Autodesk Fusion 360 part; units mm, degrees
(part 9 of 18)
  line L6313 (33.9045, -153.151) -> (33.4411, -152.779)
  line L6314 (19.1589, -158.41) -> (19.2769, -157.837)
  line L6315 (140.963, -49.9272) -> (141.518, -49.7173)
  line L6316 (23.0175, -167.339) -> (23.5183, -167.658)
  line L6317 (141.518, -49.7173) -> (142.059, -49.4711)
  line L6318 (42.7274, -154.669) -> (43.0836, -154.206)
  line L6319 (140.395, -50.0999) -> (140.963, -49.9272)
  line L6320 (23.3845, -152.323) -> (22.8893, -152.651)
  line L6321 (129.344, -157.966) -> (129.232, -158.549)
  line L6322 (146.218, -37.4969) -> (146.456, -38.0305)
  line L6323 (19.2578, -161.505) -> (19.3803, -162.086)
  line L6324 (129.38, -43.5861) -> (129.541, -44.1577)
  line L6325 (30.9627, -168.427) -> (31.5182, -168.217)
  line L6326 (41.2321, -63.7491) -> (41.1587, -64.3384)
  line L6327 (35.1334, -154.437) -> (34.7525, -153.981)
  line L6328 (146.855, -39.68) -> (146.719, -39.1021)
  line L6329 (24.2951, -151.728) -> (24.8336, -151.501)
  line L6330 (146.719, -39.1021) -> (146.544, -38.5345)
  line L6331 (130.727, -36.169) -> (131.084, -35.7057)
  line L6332 (145.483, -154.917) -> (145.133, -154.437)
  line L6333 (141.373, -151.624) -> (140.814, -151.424)
  line L6334 (41.4315, -157.274) -> (41.6223, -156.722)
  line L6335 (136.927, -50.4266) -> (136.35, -50.3337)
  line L6336 (145.801, -155.418) -> (145.483, -154.917)
  line L6337 (134.834, -33.0011) -> (135.386, -32.8094)
  line L6338 (144.453, -166.238) -> (144.856, -165.801)
  line L6339 (142.711, -33.6764) -> (143.203, -33.9917)
  line L6340 (33.0587, -167.505) -> (32.5607, -167.811)
  line L6341 (146.456, -38.0305) -> (146.659, -38.5784)
  line L6342 (133.62, -49.3267) -> (133.121, -49.0227)
  line L6343 (41.1297, -65.525) -> (41.1742, -66.1171)
  line L6344 (35.8585, -164.57) -> (35.5441, -165.063)
  line L6345 (129.974, -45.2629) -> (130.245, -45.7915)
  line L6346 (147.012, -159.357) -> (146.953, -158.766)
  line L6347 (129.777, -45.0587) -> (129.562, -44.5156)
  line L6348 (138.639, -168.887) -> (139.23, -168.83)
  line L6349 (32.4456, -152.133) -> (31.9179, -151.861)
  line L6350 (135.386, -32.8094) -> (135.949, -32.6538)
  line L6351 (146.758, -43.6467) -> (146.885, -43.0665)
  line L6352 (129.238, -43.3934) -> (129.131, -42.8189)
  line L6353 (141.518, -168.217) -> (142.059, -167.971)
  line L6354 (129.159, -39.9096) -> (129.277, -39.3373)
  line L6355 (146.885, -43.0665) -> (146.972, -42.4793)
  line L6356 (147.027, -42.7877) -> (146.922, -43.3625)
  line L6357 (45.9003, -57.2286) -> (45.3845, -57.5228)
  line L6358 (29.4301, -151.002) -> (30.0047, -151.108)
  line L6359 (146.594, -44.2172) -> (146.758, -43.6467)
  line L6360 (26.35, -168.834) -> (25.7803, -168.704)
  line L6361 (137.296, -151.029) -> (136.707, -151.1)
  line L6362 (134.039, -49.4431) -> (134.578, -49.6931)
  line L6363 (144.856, -165.801) -> (145.229, -165.339)
  line L6364 (26.7068, -151.1) -> (26.1233, -151.211)
  line L6365 (129.078, -40.4883) -> (129.159, -39.9096)
  line L6366 (28.483, -151.004) -> (27.8893, -150.997)
  line L6367 (135.132, -168.407) -> (135.699, -168.583)
  line L6368 (142.059, -167.971) -> (142.581, -167.69)
  line L6369 (132.539, -166.987) -> (133.018, -167.339)
  line L6370 (132.417, -153.01) -> (131.97, -153.401)
  line L6371 (20.466, -155.231) -> (20.17, -155.746)
  line L6372 (137.682, -32.4086) -> (138.266, -32.402)
  line L6373 (145.858, -46.0704) -> (145.544, -46.563)
  line L6374 (136.707, -151.1) -> (136.123, -151.211)
  line L6375 (142.954, -152.44) -> (142.446, -152.133)
  line L6376 (27.0994, -150.953) -> (27.682, -150.909)
  line L6377 (136.276, -50.2221) -> (136.861, -50.3221)
  line L6378 (35.6409, -154.981) -> (35.9457, -155.48)
  line L6379 (32.1995, -151.894) -> (32.7108, -152.176)
  line L6380 (135.699, -50.0835) -> (136.276, -50.2221)
  line L6381 (36.084, -155.94) -> (35.8006, -155.418)
  line L6382 (34.9379, -154.049) -> (35.3045, -154.504)
  line L6383 (142.199, -33.3936) -> (142.711, -33.6764)
  line L6384 (145.229, -46.8393) -> (145.57, -46.3534)
  line L6385 (36.6024, -162.986) -> (36.3887, -163.53)
  line L6386 (36.8847, -161.567) -> (36.9725, -160.979)
  line L6387 (147.021, -160.387) -> (147.032, -159.95)
  line L6388 (41.078, -158.988) -> (41.1589, -158.41)
  line L6389 (136.861, -168.822) -> (137.452, -168.883)
  line L6390 (131.756, -47.927) -> (131.351, -47.5056)
  line L6391 (140.243, -151.261) -> (139.663, -151.137)
  line L6392 (23.6204, -167.827) -> (23.1214, -167.523)
  line L6393 (19.1309, -161.319) -> (19.0612, -160.739)
  line L6394 (143.904, -153.151) -> (143.441, -152.779)
  line L6395 (41.1587, -64.3384) -> (41.1245, -64.9312)
  line L6396 (33.5358, -167.168) -> (33.0587, -167.505)
  line L6397 (129.035, -41.071) -> (129.078, -40.4883)
  line L6398 (21.0836, -154.206) -> (21.4688, -153.766)
  line L6399 (137.452, -50.3832) -> (138.046, -50.4049)
  line L6400 (31.671, -151.644) -> (32.1995, -151.894)
  line L6401 (41.1589, -158.41) -> (41.2769, -157.837)
  line L6402 (144.823, -47.4821) -> (144.42, -47.9049)
  line L6403 (129.029, -41.6553) -> (129.033, -41.2312)
  line L6404 (146.544, -157.035) -> (146.332, -156.48)
  line L6405 (30.2432, -151.261) -> (29.6626, -151.137)
  line L6406 (144.022, -166.647) -> (144.453, -166.238)
  line L6407 (32.0585, -167.971) -> (32.5813, -167.69)
  line L6408 (19.0347, -159.571) -> (19.078, -158.988)
  line L6409 (144.42, -47.9049) -> (143.99, -48.3008)
  line L6410 (19.3443, -157.966) -> (19.232, -158.549)
  line L6411 (43.0836, -154.206) -> (43.4688, -153.766)
  line L6412 (130.55, -46.301) -> (130.888, -46.7892)
  line L6413 (27.2963, -151.029) -> (26.7068, -151.1)
  line L6414 (28.6391, -168.887) -> (29.2302, -168.83)
  line L6415 (147.021, -41.8875) -> (147.032, -41.45)
  line L6416 (129.174, -42.4171) -> (129.258, -43.005)
  line L6417 (19.1297, -160.325) -> (19.1742, -160.917)
  line L6418 (143.203, -33.9917) -> (143.673, -34.338)
  line L6419 (34.0223, -166.647) -> (34.453, -166.238)
  line L6420 (130.466, -155.231) -> (130.17, -155.746)
  line L6421 (32.5607, -167.811) -> (32.0441, -168.084)
  line L6422 (144.453, -47.7378) -> (144.856, -47.3014)
  line L6423 (35.8006, -155.418) -> (35.4833, -154.917)
  line L6424 (37.0274, -161.288) -> (36.9224, -161.862)
  line L6425 (29.075, -151.051) -> (28.483, -151.004)
  line L6426 (26.5208, -151.035) -> (27.0994, -150.953)
  line L6427 (19.541, -162.658) -> (19.7392, -163.217)
  line L6428 (36.7806, -162.429) -> (36.6024, -162.986)
  line L6429 (30.0047, -151.108) -> (30.5713, -151.251)
  line L6430 (131.882, -34.8528) -> (132.32, -34.4668)
  line L6431 (145.57, -46.3534) -> (145.879, -45.846)
  line L6432 (146.332, -156.48) -> (146.084, -155.94)
  line L6433 (131.469, -35.2664) -> (131.882, -34.8528)
  line L6434 (146.659, -38.5784) -> (146.827, -39.1382)
  line L6435 (25.9488, -151.154) -> (26.5208, -151.035)
  line L6436 (23.1214, -167.523) -> (22.643, -167.187)
  line L6437 (129.258, -43.005) -> (129.38, -43.5861)
  line L6438 (19.1742, -160.917) -> (19.2578, -161.505)
  line L6439 (147.012, -40.8565) -> (146.953, -40.2656)
  line L6440 (34.7525, -153.981) -> (34.3423, -153.552)
  line L6441 (132.643, -48.6871) -> (132.187, -48.3214)
  line L6442 (20.402, -155.154) -> (20.7274, -154.669)
  line L6443 (21.2572, -165.754) -> (21.6569, -166.193)
  line L6444 (147.108, -40.866) -> (147.127, -41.45)
  line L6445 (131.657, -166.193) -> (132.085, -166.605)
  line L6446 (143.565, -48.5258) -> (144.022, -48.1465)
  line L6447 (21.4688, -153.766) -> (21.8816, -153.353)
  line L6448 (129.033, -41.2312) -> (129.035, -41.071)
  line L6449 (140.814, -151.424) -> (140.243, -151.261)
  line L6450 (30.8143, -151.424) -> (30.2432, -151.261)
  line L6451 (132.187, -48.3214) -> (131.756, -47.927)
  line L6452 (145.641, -36.4813) -> (145.946, -36.9798)
  line L6453 (31.3734, -151.624) -> (30.8143, -151.424)
  line L6454 (129.277, -39.3373) -> (129.432, -38.7738)
  line L6455 (143.059, -49.0054) -> (142.561, -49.3111)
  line L6456 (133.121, -49.0227) -> (132.643, -48.6871)
  line L6457 (133.772, -33.4892) -> (134.295, -33.228)
  line L6458 (20.2446, -164.291) -> (20.5495, -164.801)
  line L6459 (136.35, -50.3337) -> (135.78, -50.2038)
  line L6460 (143.536, -48.6681) -> (143.059, -49.0054)
  line L6461 (135.699, -168.583) -> (136.276, -168.722)
  line L6462 (19.4315, -157.274) -> (19.6222, -156.722)
  line L6463 (22.0847, -166.605) -> (22.539, -166.987)
  line L6464 (20.1085, -155.66) -> (20.402, -155.154)
  line L6465 (20.9746, -165.559) -> (20.6274, -165.089)
  line L6466 (129.683, -156.829) -> (129.495, -157.392)
  line L6467 (133.518, -167.658) -> (134.039, -167.943)
  line L6468 (142.561, -49.3111) -> (142.044, -49.5841)
  line L6469 (43.157, -59.466) -> (42.7955, -59.9371)
  line L6470 (147.051, -40.2844) -> (147.108, -40.866)
  line L6471 (132.539, -48.4873) -> (133.018, -48.8389)
  line L6472 (141.128, -32.9297) -> (141.671, -33.1443)
  line L6473 (146.544, -38.5345) -> (146.332, -37.9798)
  line L6474 (132.32, -34.4668) -> (132.783, -34.1099)
  line L6475 (133.385, -152.323) -> (132.889, -152.651)
  line L6476 (35.1986, -165.534) -> (34.8234, -165.982)
  line L6477 (41.1245, -64.9312) -> (41.1297, -65.525)
  line L6478 (35.57, -164.853) -> (35.8785, -164.346)
  line L6479 (25.6987, -168.583) -> (26.2761, -168.722)
  line L6480 (42.17, -60.9459) -> (41.9088, -61.4791)
  line L6481 (19.9741, -163.763) -> (20.2446, -164.291)
  line L6482 (131.351, -47.5056) -> (130.975, -47.059)
  line L6483 (20.7955, -154.737) -> (20.466, -155.231)
  line L6484 (163.518, -168.217) -> (164.059, -167.971)
  line L6485 (164.446, -152.133) -> (163.918, -151.861)
  line L6486 (45.9003, -152.029) -> (45.3845, -152.323)
  line L6487 (81.0274, -161.288) -> (80.9224, -161.862)
  line L6488 (163.671, -151.644) -> (164.199, -151.894)
  line L6489 (66.539, -166.987) -> (67.0175, -167.339)
  line L6490 (152.245, -164.291) -> (152.55, -164.801)
  line L6491 (112.672, -168.335) -> (112.138, -168.098)
  line L6492 (46.4345, -151.769) -> (45.9003, -152.029)
  line L6493 (151.035, -159.571) -> (151.078, -158.988)
  line L6494 (58.1527, -163.819) -> (58.3914, -163.276)
  line L6495 (151.495, -157.392) -> (151.344, -157.966)
  line L6496 (151.124, -159.731) -> (151.13, -160.325)
  line L6497 (63.2379, -161.893) -> (63.1309, -161.319)
  line L6498 (78.453, -166.238) -> (78.8557, -165.801)
  line L6499 (80.3321, -156.48) -> (80.084, -155.94)
  line L6500 (58.9725, -160.979) -> (59.0211, -160.387)
  line L6501 (166.342, -153.552) -> (165.904, -153.151)
  line L6502 (125.127, -159.95) -> (125.125, -160.124)
  line L6503 (58.3914, -163.276) -> (58.5935, -162.717)
  line L6504 (159.296, -151.029) -> (158.707, -151.1)
  line L6505 (73.8346, -168.828) -> (73.2581, -168.923)
  line L6506 (168.602, -162.986) -> (168.389, -163.53)
  line L6507 (49.2963, -151.029) -> (48.7068, -151.1)
  line L6508 (71.4521, -168.883) -> (72.0455, -168.905)
  line L6509 (124.781, -162.429) -> (124.602, -162.986)
  line L6510 (117.835, -168.828) -> (117.258, -168.923)
  line L6511 (46.9847, -151.546) -> (46.4345, -151.769)
  line L6512 (160.677, -168.98) -> (160.093, -169)
  line L6513 (47.5484, -151.359) -> (46.9847, -151.546)
  line L6514 (63.9741, -163.763) -> (64.2446, -164.291)
  line L6515 (48.1233, -151.211) -> (47.5484, -151.359)
  line L6516 (72.6391, -168.887) -> (73.2302, -168.83)
  line L6517 (48.7068, -151.1) -> (48.1233, -151.211)
  line L6518 (168.719, -157.602) -> (168.544, -157.035)
  line L6519 (115.509, -168.982) -> (114.927, -168.927)
  line L6520 (156.672, -168.335) -> (156.138, -168.098)
  line L6521 (65.8816, -153.353) -> (66.3203, -152.967)
  line L6522 (81.0514, -158.784) -> (81.1079, -159.366)
  line L6523 (53.3734, -151.624) -> (52.8143, -151.424)
  line L6524 (151.174, -160.917) -> (151.258, -161.505)
  line L6525 (156.039, -167.943) -> (156.578, -168.193)
  line L6526 (161.258, -168.923) -> (160.677, -168.98)
  line L6527 (123.544, -165.063) -> (123.199, -165.534)
  line L6528 (169.125, -160.124) -> (169.095, -160.707)
  line L6529 (151.277, -157.837) -> (151.432, -157.274)
  line L6530 (151.078, -158.988) -> (151.159, -158.41)
  line L6531 (69.3856, -151.309) -> (69.9488, -151.154)
  line L6532 (151.159, -159.138) -> (151.124, -159.731)
  line L6533 (166.856, -165.801) -> (167.229, -165.339)
  line L6534 (151.159, -158.41) -> (151.277, -157.837)
  line L6535 (80.5935, -162.717) -> (80.7582, -162.147)
  line L6536 (120.044, -168.084) -> (119.511, -168.323)
  line L6537 (153.257, -165.754) -> (153.657, -166.193)
  line L6538 (151.432, -157.274) -> (151.622, -156.722)
  line L6539 (158.861, -168.822) -> (159.452, -168.883)
  line L6540 (65.2572, -165.754) -> (65.6569, -166.193)
  line L6541 (151.033, -159.731) -> (151.035, -159.571)
  line L6542 (79.6409, -154.981) -> (79.9457, -155.48)
  line L6543 (124.922, -161.862) -> (124.781, -162.429)
  line L6544 (66.7829, -152.61) -> (67.2676, -152.284)
  line L6545 (51.6626, -151.137) -> (51.075, -151.051)
  line L6546 (168.781, -162.429) -> (168.602, -162.986)
  line L6547 (55.9045, -153.151) -> (55.4411, -152.779)
  line L6548 (168.544, -157.035) -> (168.332, -156.48)
  line L6549 (80.3887, -163.53) -> (80.1404, -164.059)
  line L6550 (41.1297, -160.325) -> (41.1742, -160.917)
  line L6551 (168.456, -156.531) -> (168.659, -157.078)
  line L6552 (77.9903, -166.801) -> (77.5358, -167.168)
  line L6553 (155.121, -167.523) -> (154.643, -167.187)
  line L6554 (80.7582, -162.147) -> (80.8847, -161.567)
  line L6555 (41.1245, -159.731) -> (41.1297, -160.325)
  line L6556 (154.085, -166.605) -> (154.539, -166.987)
  line L6557 (125.051, -158.784) -> (125.108, -159.366)
  line L6558 (68.672, -168.335) -> (68.138, -168.098)
  line L6559 (67.7724, -151.989) -> (68.2951, -151.728)
  line L6560 (151.232, -158.549) -> (151.159, -159.138)
  line L6561 (157.22, -168.537) -> (156.672, -168.335)
  line L6562 (154.417, -153.01) -> (153.97, -153.401)
  line L6563 (166.823, -165.982) -> (166.42, -166.405)
  line L6564 (69.9488, -151.154) -> (70.5208, -151.035)
  line L6565 (63.078, -158.988) -> (63.1589, -158.41)
  line L6566 (73.8162, -168.734) -> (74.3945, -168.6)
  line L6567 (80.4559, -156.531) -> (80.6591, -157.078)
  line L6568 (41.1587, -159.138) -> (41.1245, -159.731)
  line L6569 (162.963, -168.527) -> (162.404, -168.696)
  line L6570 (168.957, -158.208) -> (169.051, -158.784)
  line L6571 (81.0121, -159.357) -> (80.9531, -158.766)
  line L6572 (155.518, -167.658) -> (156.039, -167.943)
  line L6573 (80.7806, -162.429) -> (80.6024, -162.986)
  line L6574 (63.4315, -157.274) -> (63.6222, -156.722)
  line L6575 (80.2178, -155.997) -> (80.4559, -156.531)
  line L6576 (53.9179, -151.861) -> (53.3734, -151.624)
  line L6577 (113.22, -168.537) -> (112.672, -168.335)
  line L6578 (79.1986, -165.534) -> (78.8234, -165.982)
  line L6579 (79.8585, -164.57) -> (79.5441, -165.063)
  line L6580 (159.889, -150.997) -> (159.296, -151.029)
  line L6581 (168.885, -161.567) -> (168.972, -160.979)
  line L6582 (81.0318, -159.95) -> (81.0121, -159.357)
  line L6583 (54.4456, -152.133) -> (53.9179, -151.861)
  line L6584 (80.9531, -158.766) -> (80.8551, -158.18)
  line L6585 (168.389, -163.53) -> (168.14, -164.059)
  line L6586 (80.6024, -162.986) -> (80.3887, -163.53)
  line L6587 (54.954, -152.44) -> (54.4456, -152.133)
  line L6588 (164.199, -151.894) -> (164.711, -152.176)
  line L6589 (41.2321, -158.549) -> (41.1587, -159.138)
  line L6590 (153.756, -166.427) -> (153.351, -166.006)
  line L6591 (73.4301, -151.002) -> (74.0047, -151.108)
  line L6592 (159.452, -168.883) -> (160.046, -168.905)
  line L6593 (68.8336, -151.501) -> (69.3856, -151.309)
  line L6594 (52.2432, -151.261) -> (51.6626, -151.137)
  line L6595 (151.061, -160.739) -> (151.029, -160.155)
  line L6596 (166.543, -153.618) -> (166.938, -154.049)
  line L6597 (78.9379, -154.049) -> (79.3045, -154.504)
  line L6598 (166.453, -166.238) -> (166.856, -165.801)
  line L6599 (41.3443, -157.966) -> (41.2321, -158.549)
  line L6600 (117.258, -168.923) -> (116.677, -168.98)
  line L6601 (41.495, -157.392) -> (41.3443, -157.966)
  line L6602 (151.541, -162.658) -> (151.739, -163.217)
  line L6603 (63.3803, -162.086) -> (63.541, -162.658)
  line L6604 (154.643, -167.187) -> (154.187, -166.821)
  line L6605 (165.565, -167.026) -> (166.022, -166.647)
  line L6606 (70.5208, -151.035) -> (71.0994, -150.953)
  line L6607 (67.2676, -152.284) -> (67.7724, -151.989)
  line L6608 (165.203, -152.492) -> (165.673, -152.838)
  line L6609 (69.7803, -168.704) -> (69.2202, -168.537)
  line L6610 (49.8893, -150.997) -> (49.2963, -151.029)
  line L6611 (67.0175, -167.339) -> (67.5183, -167.658)
  line L6612 (67.6204, -167.827) -> (67.1214, -167.523)
  line L6613 (156.138, -168.098) -> (155.62, -167.827)
  line L6614 (80.1527, -163.819) -> (80.3914, -163.276)
  line L6615 (167.544, -165.063) -> (167.199, -165.534)
  line L6616 (41.9088, -156.279) -> (41.6834, -156.829)
  line L6617 (41.6834, -156.829) -> (41.495, -157.392)
  line L6618 (74.9627, -168.427) -> (75.5182, -168.217)
  line L6619 (166.022, -166.647) -> (166.453, -166.238)
  line L6620 (167.946, -155.48) -> (168.218, -155.997)
  line L6621 (151.344, -157.966) -> (151.232, -158.549)
  line L6622 (167.229, -165.339) -> (167.57, -164.853)
  line L6623 (57.4833, -154.917) -> (57.1334, -154.437)
  line L6624 (168.972, -160.979) -> (169.021, -160.387)
  line L6625 (63.0332, -159.731) -> (63.0347, -159.571)
  line L6626 (75.671, -151.644) -> (76.1995, -151.894)
  line L6627 (160.093, -169) -> (159.509, -168.982)
  line L6628 (152.55, -164.801) -> (152.888, -165.289)
  line L6629 (42.17, -155.746) -> (41.9088, -156.279)
  line L6630 (76.5813, -167.69) -> (77.0844, -167.374)
  line L6631 (155.018, -167.339) -> (155.518, -167.658)
  line L6632 (154.539, -166.987) -> (155.018, -167.339)
  line L6633 (165.536, -167.168) -> (165.059, -167.505)
  line L6634 (42.466, -155.231) -> (42.17, -155.746)
  line L6635 (64.402, -155.154) -> (64.7274, -154.669)
  line L6636 (66.643, -167.187) -> (66.1873, -166.821)
  line L6637 (155.9, -152.029) -> (155.385, -152.323)
  line L6638 (167.304, -154.504) -> (167.641, -154.981)
  line L6639 (165.99, -166.801) -> (165.536, -167.168)
  line L6640 (71.0994, -150.953) -> (71.682, -150.909)
  line L6641 (168.659, -157.078) -> (168.827, -157.638)
  line L6642 (151.131, -161.319) -> (151.061, -160.739)
  line L6643 (66.3203, -152.967) -> (66.7829, -152.61)
  line L6644 (69.6987, -168.583) -> (70.2761, -168.722)
  line L6645 (80.5439, -157.035) -> (80.3321, -156.48)
  line L6646 (166.121, -153.214) -> (166.543, -153.618)
  line L6647 (153.549, -153.82) -> (153.157, -154.266)
  line L6648 (42.7955, -154.737) -> (42.466, -155.231)
  line L6649 (43.157, -154.266) -> (42.7955, -154.737)
  line L6650 (152.17, -155.746) -> (151.909, -156.279)
  line L6651 (162.963, -168.427) -> (163.518, -168.217)
  line L6652 (114.35, -168.834) -> (113.78, -168.704)
  line L6653 (157.132, -168.407) -> (157.699, -168.583)
  line L6654 (58.5439, -157.035) -> (58.3321, -156.48)
  line L6655 (125.108, -159.366) -> (125.127, -159.95)
  line L6656 (58.9531, -158.766) -> (58.8551, -158.18)
  line L6657 (125.027, -161.288) -> (124.922, -161.862)
  line L6658 (77.6734, -152.838) -> (78.1207, -153.214)
  line L6659 (64.6274, -165.089) -> (64.3113, -164.598)
  line L6660 (43.5489, -153.82) -> (43.157, -154.266)
  line L6661 (161.835, -168.828) -> (161.258, -168.923)
  line L6662 (70.9269, -168.927) -> (70.35, -168.834)
  line L6663 (167.483, -154.917) -> (167.133, -154.437)
  line L6664 (156.985, -151.546) -> (156.434, -151.769)
  line L6665 (43.9695, -153.401) -> (43.5489, -153.82)
  line L6666 (156.578, -168.193) -> (157.132, -168.407)
  line L6667 (63.7774, -163.559) -> (63.5618, -163.016)
  line L6668 (161.075, -151.051) -> (160.483, -151.004)
  line L6669 (113.78, -168.704) -> (113.22, -168.537)
  line L6670 (116.677, -168.98) -> (116.093, -169)
  line L6671 (169.095, -160.707) -> (169.027, -161.288)
  line L6672 (57.8785, -164.346) -> (58.1527, -163.819)
  line L6673 (169.127, -159.95) -> (169.125, -160.124)
  line L6674 (162.404, -168.696) -> (161.835, -168.828)
  line L6675 (158.927, -168.927) -> (158.35, -168.834)
  line L6676 (78.0223, -166.647) -> (78.453, -166.238)
  line L6677 (78.8557, -165.801) -> (79.2286, -165.339)
  line L6678 (168.391, -163.276) -> (168.594, -162.717)
  line L6679 (119.511, -168.323) -> (118.963, -168.527)
  line L6680 (44.417, -153.01) -> (43.9695, -153.401)
  line L6681 (114.927, -168.927) -> (114.35, -168.834)
  line L6682 (125.125, -160.124) -> (125.095, -160.707)
  line L6683 (162.395, -168.6) -> (162.963, -168.427)
  line L6684 (151.382, -162.46) -> (151.238, -161.893)
  line L6685 (59.0318, -159.95) -> (59.0121, -159.357)
  line L6686 (151.683, -156.829) -> (151.495, -157.392)
  line L6687 (151.029, -160.155) -> (151.033, -159.731)
  line L6688 (74.5713, -151.251) -> (75.1275, -151.43)
  line L6689 (165.084, -167.374) -> (165.565, -167.026)
  line L6690 (72.0926, -169) -> (71.5085, -168.982)
  line L6691 (75.5109, -168.323) -> (74.9634, -168.527)
  line L6692 (68.2951, -151.728) -> (68.8336, -151.501)
  line L6693 (121.059, -167.505) -> (120.561, -167.811)
  line L6694 (163.511, -168.323) -> (162.963, -168.527)
  line L6695 (59.0121, -159.357) -> (58.9531, -158.766)
  line L6696 (64.2446, -164.291) -> (64.5495, -164.801)
  line L6697 (151.739, -163.217) -> (151.974, -163.763)
  line L6698 (44.8893, -152.651) -> (44.417, -153.01)
  line L6699 (168.953, -158.766) -> (168.855, -158.18)
  line L6700 (59.0211, -160.387) -> (59.0318, -159.95)
  line L6701 (81.1079, -159.366) -> (81.1268, -159.95)
  line L6702 (68.0392, -167.943) -> (68.5778, -168.193)
  line L6703 (168.758, -162.147) -> (168.885, -161.567)
  line L6704 (67.1214, -167.523) -> (66.643, -167.187)
  line L6705 (63.541, -162.658) -> (63.7392, -163.217)
  line L6706 (157.78, -168.704) -> (157.22, -168.537)
  line L6707 (57.57, -164.853) -> (57.8785, -164.346)
  line L6708 (58.7582, -162.147) -> (58.8847, -161.567)
  line L6709 (45.3845, -152.323) -> (44.8893, -152.651)
  line L6710 (153.157, -154.266) -> (152.795, -154.737)
  line L6711 (168.332, -156.48) -> (168.084, -155.94)
  line L6712 (124.389, -163.53) -> (124.14, -164.059)
  line L6713 (154.889, -152.651) -> (154.417, -153.01)
  line L6714 (158.35, -168.834) -> (157.78, -168.704)
  line L6715 (65.0836, -154.206) -> (65.4688, -153.766)
  line L6716 (168.922, -161.862) -> (168.781, -162.429)
  line L6717 (80.9575, -158.208) -> (81.0514, -158.784)
  line L6718 (58.5935, -162.717) -> (58.7582, -162.147)
  line L6719 (159.509, -168.982) -> (158.927, -168.927)
  line L6720 (58.8847, -161.567) -> (58.9725, -160.979)
  line L6721 (123.199, -165.534) -> (122.823, -165.982)
  line L6722 (152.466, -155.231) -> (152.17, -155.746)
  line L6723 (79.57, -164.853) -> (79.8785, -164.346)
  line L6724 (164.561, -167.811) -> (164.044, -168.084)
  line L6725 (65.7561, -166.427) -> (65.3513, -166.006)
  line L6726 (169.027, -161.288) -> (168.922, -161.862)
  line L6727 (75.5182, -168.217) -> (76.0585, -167.971)
  line L6728 (169.032, -159.95) -> (169.012, -159.357)
  line L6729 (81.1268, -159.95) -> (81.1251, -160.124)
  line L6730 (168.855, -158.18) -> (168.719, -157.602)
  line L6731 (162.571, -151.251) -> (163.128, -151.43)
  line L6732 (163.128, -151.43) -> (163.671, -151.644)
  line L6733 (167.879, -164.346) -> (168.153, -163.819)
  line L6734 (124.14, -164.059) -> (123.858, -164.57)
  line L6735 (165.441, -152.779) -> (164.954, -152.44)
  line L6736 (70.2761, -168.722) -> (70.8615, -168.822)
  line L6737 (81.0211, -160.387) -> (81.0318, -159.95)
  line L6738 (152.402, -155.154) -> (152.727, -154.669)
  line L6739 (168.218, -155.997) -> (168.456, -156.531)
  line L6740 (73.2302, -168.83) -> (73.8162, -168.734)
  line L6741 (63.2769, -157.837) -> (63.4315, -157.274)
  line L6742 (157.548, -151.359) -> (156.985, -151.546)
  line L6743 (167.57, -164.853) -> (167.879, -164.346)
  line L6744 (70.8615, -168.822) -> (71.4521, -168.883)
  line L6745 (51.075, -151.051) -> (50.483, -151.004)
  line L6746 (58.7185, -157.602) -> (58.5439, -157.035)
  line L6747 (158.276, -168.722) -> (158.861, -168.822)
  line L6748 (79.3045, -154.504) -> (79.6409, -154.981)
  line L6749 (72.2663, -150.902) -> (72.8498, -150.933)
  line L6750 (163.918, -151.861) -> (163.373, -151.624)
  line L6751 (168.827, -157.638) -> (168.957, -158.208)
  line L6752 (65.4688, -153.766) -> (65.8816, -153.353)
  line L6753 (65.3513, -166.006) -> (64.9746, -165.559)
  line L6754 (63.8482, -156.183) -> (64.1085, -155.66)
  line L6755 (153.084, -154.206) -> (153.469, -153.766)
  line L6756 (79.8785, -164.346) -> (80.1527, -163.819)
  line L6757 (151.848, -156.183) -> (152.108, -155.66)
  line L6758 (79.5441, -165.063) -> (79.1986, -165.534)
  line L6759 (68.138, -168.098) -> (67.6204, -167.827)
  line L6760 (151.622, -156.722) -> (151.848, -156.183)
  line L6761 (152.028, -164.087) -> (151.777, -163.559)
  line L6762 (65.6569, -166.193) -> (66.0847, -166.605)
  line L6763 (122.823, -165.982) -> (122.42, -166.405)
  line L6764 (58.084, -155.94) -> (57.8006, -155.418)
  line L6765 (63.1589, -158.41) -> (63.2769, -157.837)
  line L6766 (66.0847, -166.605) -> (66.539, -166.987)
  line L6767 (66.1873, -166.821) -> (65.7561, -166.427)
  line L6768 (80.8266, -157.638) -> (80.9575, -158.208)
  line L6769 (77.5358, -167.168) -> (77.0587, -167.505)
  line L6770 (80.7185, -157.602) -> (80.5439, -157.035)
  line L6771 (168.14, -164.059) -> (167.858, -164.57)
  line L6772 (165.673, -152.838) -> (166.121, -153.214)
  line L6773 (63.1309, -161.319) -> (63.0612, -160.739)
  line L6774 (63.2578, -161.505) -> (63.3803, -162.086)
  line L6775 (167.858, -164.57) -> (167.544, -165.063)
  line L6776 (64.3113, -164.598) -> (64.0276, -164.087)
  line L6777 (167.641, -154.981) -> (167.946, -155.48)
  line L6778 (165.904, -153.151) -> (165.441, -152.779)
  line L6779 (58.3321, -156.48) -> (58.084, -155.94)
  line L6780 (161.663, -151.137) -> (161.075, -151.051)
  line L6781 (77.0587, -167.505) -> (76.5607, -167.811)
  line L6782 (152.108, -155.66) -> (152.402, -155.154)
  line L6783 (80.1404, -164.059) -> (79.8585, -164.57)
  line L6784 (169.012, -159.357) -> (168.953, -158.766)
  line L6785 (55.4411, -152.779) -> (54.954, -152.44)
  line L6786 (164.711, -152.176) -> (165.203, -152.492)
  line L6787 (153.882, -153.353) -> (154.32, -152.967)
  line L6788 (74.3945, -168.6) -> (74.9627, -168.427)
  line L6789 (152.975, -165.559) -> (152.627, -165.089)
  line L6790 (152.727, -154.669) -> (153.084, -154.206)
  line L6791 (63.3817, -162.46) -> (63.2379, -161.893)
  line L6792 (155.772, -151.989) -> (156.295, -151.728)
  line L6793 (80.9224, -161.862) -> (80.7806, -162.429)
  line L6794 (76.7108, -152.176) -> (77.2028, -152.492)
  line L6795 (80.8847, -161.567) -> (80.9725, -160.979)
  line L6796 (166.42, -166.405) -> (165.99, -166.801)
  line L6797 (63.1742, -160.917) -> (63.2578, -161.505)
  line L6798 (165.059, -167.505) -> (164.561, -167.811)
  line L6799 (160.483, -151.004) -> (159.889, -150.997)
  line L6800 (77.5654, -167.026) -> (78.0223, -166.647)
  line L6801 (63.0291, -160.155) -> (63.0332, -159.731)
  line L6802 (161.23, -168.83) -> (161.816, -168.734)
  line L6803 (64.7274, -154.669) -> (65.0836, -154.206)
  line L6804 (72.6766, -168.98) -> (72.0926, -169)
  line L6805 (79.2286, -165.339) -> (79.57, -164.853)
  line L6806 (151.38, -162.086) -> (151.541, -162.658)
  line L6807 (154.32, -152.967) -> (154.783, -152.61)
  line L6808 (77.2028, -152.492) -> (77.6734, -152.838)
  line L6809 (78.8234, -165.982) -> (78.42, -166.405)
  line L6810 (164.581, -167.69) -> (165.084, -167.374)
  line L6811 (72.0455, -168.905) -> (72.6391, -168.887)
  line L6812 (70.35, -168.834) -> (69.7803, -168.704)
  line L6813 (162.814, -151.424) -> (162.243, -151.261)
  line L6814 (153.351, -166.006) -> (152.975, -165.559)
  line L6815 (67.5183, -167.658) -> (68.0392, -167.943)
  line L6816 (116.093, -169) -> (115.509, -168.982)
  line L6817 (76.1995, -151.894) -> (76.7108, -152.176)
  line L6818 (157.699, -168.583) -> (158.276, -168.722)
  line L6819 (158.521, -151.035) -> (159.099, -150.953)
  line L6820 (156.434, -151.769) -> (155.9, -152.029)
  line L6821 (156.295, -151.728) -> (156.834, -151.501)
  line L6822 (80.6591, -157.078) -> (80.8266, -157.638)
  line L6823 (63.6222, -156.722) -> (63.8482, -156.183)
  line L6824 (153.469, -153.766) -> (153.882, -153.353)
  line L6825 (152.888, -165.289) -> (153.257, -165.754)
  line L6826 (58.8551, -158.18) -> (58.7185, -157.602)
  line L6827 (81.0951, -160.707) -> (81.0274, -161.288)
  line L6828 (50.483, -151.004) -> (49.8893, -150.997)
  line L6829 (167.133, -154.437) -> (166.753, -153.981)
  line L6830 (162.243, -151.261) -> (161.663, -151.137)
  line L6831 (76.0441, -168.084) -> (75.5109, -168.323)
  line L6832 (81.1251, -160.124) -> (81.0951, -160.707)
  line L6833 (78.42, -166.405) -> (77.9903, -166.801)
  line L6834 (64.0276, -164.087) -> (63.7774, -163.559)
  line L6835 (63.0347, -159.571) -> (63.078, -158.988)
  line L6836 (76.5607, -167.811) -> (76.0441, -168.084)
  line L6837 (168.153, -163.819) -> (168.391, -163.276)
  line L6838 (152.795, -154.737) -> (152.466, -155.231)
  line L6839 (64.5495, -164.801) -> (64.8876, -165.289)
  line L6840 (151.238, -161.893) -> (151.131, -161.319)
  line L6841 (74.9634, -168.527) -> (74.4039, -168.696)
  line L6842 (159.099, -150.953) -> (159.682, -150.909)
  line L6843 (118.404, -168.696) -> (117.835, -168.828)
  line L6844 (153.97, -153.401) -> (153.549, -153.82)
  line L6845 (169.021, -160.387) -> (169.032, -159.95)
  line L6846 (52.8143, -151.424) -> (52.2432, -151.261)
  line L6847 (157.386, -151.309) -> (157.949, -151.154)
  line L6848 (78.5428, -153.618) -> (78.9379, -154.049)
  line L6849 (57.8006, -155.418) -> (57.4833, -154.917)
  line L6850 (151.258, -161.505) -> (151.38, -162.086)
  line L6851 (166.753, -153.981) -> (166.342, -153.552)
  line L6852 (154.187, -166.821) -> (153.756, -166.427)
  line L6853 (79.9457, -155.48) -> (80.2178, -155.997)
  line L6854 (152.627, -165.089) -> (152.311, -164.598)
  line L6855 (163.373, -151.624) -> (162.814, -151.424)
  line L6856 (56.3423, -153.552) -> (55.9045, -153.151)
  line L6857 (159.682, -150.909) -> (160.266, -150.902)
  line L6858 (154.783, -152.61) -> (155.268, -152.284)
  line L6859 (155.62, -167.827) -> (155.121, -167.523)
  line L6860 (164.059, -167.971) -> (164.581, -167.69)
  line L6861 (160.266, -150.902) -> (160.85, -150.933)
  line L6862 (155.268, -152.284) -> (155.772, -151.989)
  line L6863 (161.816, -168.734) -> (162.395, -168.6)
  line L6864 (71.5085, -168.982) -> (70.9269, -168.927)
  line L6865 (74.0047, -151.108) -> (74.5713, -151.251)
  line L6866 (74.4039, -168.696) -> (73.8346, -168.828)
  line L6867 (123.858, -164.57) -> (123.544, -165.063)
  line L6868 (121.99, -166.801) -> (121.536, -167.168)
  line L6869 (71.682, -150.909) -> (72.2663, -150.902)
  line L6870 (122.42, -166.405) -> (121.99, -166.801)
  line L6871 (73.2581, -168.923) -> (72.6766, -168.98)
  line L6872 (69.1318, -168.407) -> (69.6987, -168.583)
  line L6873 (120.561, -167.811) -> (120.044, -168.084)
  line L6874 (68.5778, -168.193) -> (69.1318, -168.407)
  line L6875 (57.1334, -154.437) -> (56.7525, -153.981)
  line L6876 (77.0844, -167.374) -> (77.5654, -167.026)
  line L6877 (167.199, -165.534) -> (166.823, -165.982)
  line L6878 (69.2202, -168.537) -> (68.672, -168.335)
  line L6879 (168.594, -162.717) -> (168.758, -162.147)
  line L6880 (158.123, -151.211) -> (157.548, -151.359)
  line L6881 (164.044, -168.084) -> (163.511, -168.323)
  line L6882 (121.536, -167.168) -> (121.059, -167.505)
  line L6883 (156.834, -151.501) -> (157.386, -151.309)
  line L6884 (76.0585, -167.971) -> (76.5813, -167.69)
  line L6885 (63.0612, -160.739) -> (63.0291, -160.155)
  line L6886 (63.7392, -163.217) -> (63.9741, -163.763)
  line L6887 (72.8498, -150.933) -> (73.4301, -151.002)
  line L6888 (167.801, -155.418) -> (167.483, -154.917)
  line L6889 (80.8551, -158.18) -> (80.7185, -157.602)
  line L6890 (155.385, -152.323) -> (154.889, -152.651)
  line L6891 (161.43, -151.002) -> (162.005, -151.108)
  line L6892 (153.657, -166.193) -> (154.085, -166.605)
  line L6893 (162.005, -151.108) -> (162.571, -151.251)
  line L6894 (56.7525, -153.981) -> (56.3423, -153.552)
  line L6895 (151.777, -163.559) -> (151.562, -163.016)
  line L6896 (152.311, -164.598) -> (152.028, -164.087)
  line L6897 (157.949, -151.154) -> (158.521, -151.035)
  line L6898 (118.963, -168.527) -> (118.404, -168.696)
  line L6899 (160.046, -168.905) -> (160.639, -168.887)
  line L6900 (125.095, -160.707) -> (125.027, -161.288)
  line L6901 (151.13, -160.325) -> (151.174, -160.917)
  line L6902 (80.3914, -163.276) -> (80.5935, -162.717)
  line L6903 (158.707, -151.1) -> (158.123, -151.211)
  line L6904 (160.85, -150.933) -> (161.43, -151.002)
  line L6905 (166.938, -154.049) -> (167.304, -154.504)
  line L6906 (169.051, -158.784) -> (169.108, -159.366)
  line L6907 (160.639, -168.887) -> (161.23, -168.83)
  line L6908 (75.1275, -151.43) -> (75.671, -151.644)
  line L6909 (80.9725, -160.979) -> (81.0211, -160.387)
  line L6910 (64.8876, -165.289) -> (65.2572, -165.754)
  line L6911 (78.1207, -153.214) -> (78.5428, -153.618)
  line L6912 (64.9746, -165.559) -> (64.6274, -165.089)
  line L6913 (151.974, -163.763) -> (152.245, -164.291)
  line L6914 (151.562, -163.016) -> (151.382, -162.46)
  line L6915 (63.5618, -163.016) -> (63.3817, -162.46)
  line L6916 (169.108, -159.366) -> (169.127, -159.95)
  line L6917 (64.1085, -155.66) -> (64.402, -155.154)
  line L6918 (124.602, -162.986) -> (124.389, -163.53)
  line L6919 (164.954, -152.44) -> (164.446, -152.133)
  line L6920 (168.084, -155.94) -> (167.801, -155.418)
  line L6921 (151.909, -156.279) -> (151.683, -156.829)
  line L6922 (99.4411, -34.2794) -> (98.954, -33.9397)
  line L6923 (102.758, -43.6467) -> (102.885, -43.0665)
  line L6924 (89.0175, -48.8389) -> (89.5183, -49.1579)
  line L6925 (109.084, -35.7057) -> (109.469, -35.2664)
  line L6926 (91.6987, -50.0835) -> (92.2761, -50.2221)
  line L6927 (110.32, -34.4668) -> (110.783, -34.1099)
  line L6928 (86.2446, -45.7915) -> (86.5495, -46.301)
  line L6929 (108.108, -37.1595) -> (108.402, -36.6542)
  line L6930 (103.032, -41.45) -> (103.012, -40.8565)
  line L6931 (111.772, -33.4892) -> (112.295, -33.228)
  line L6932 (85.7774, -45.0587) -> (85.5618, -44.5156)
  line L6933 (103.012, -40.8565) -> (102.953, -40.2656)
  line L6934 (102.953, -40.2656) -> (102.855, -39.68)
  line L6935 (88.1873, -48.3214) -> (87.7561, -47.927)
  line L6936 (120.199, -33.3936) -> (120.711, -33.6764)
  line L6937 (107.432, -38.7738) -> (107.622, -38.2215)
  line L6938 (107.622, -38.2215) -> (107.848, -37.6827)
  line L6939 (100.753, -35.4812) -> (100.342, -35.0519)
  line L6940 (111.268, -33.7835) -> (111.772, -33.4892)
  line L6941 (114.521, -32.5348) -> (115.099, -32.4529)
  line L6942 (85.0612, -42.2388) -> (85.0291, -41.6553)
  line L6943 (107.848, -37.6827) -> (108.108, -37.1595)
  line L6944 (113.949, -32.6538) -> (114.521, -32.5348)
  line L6945 (121.203, -33.9917) -> (121.673, -34.338)
  line L6946 (122.121, -34.714) -> (122.543, -35.118)
  line L6947 (108.402, -36.6542) -> (108.727, -36.169)
  line L6948 (89.9003, -33.5286) -> (89.3845, -33.8228)
  line L6949 (85.9741, -45.2629) -> (86.2446, -45.7915)
  line L6950 (121.673, -34.338) -> (122.121, -34.714)
  line L6951 (85.6834, -38.3285) -> (85.495, -38.8917)
  line L6952 (93.4521, -50.3832) -> (94.0455, -50.4049)
  line L6953 (87.5489, -35.3199) -> (87.157, -35.766)
  line L6954 (102.719, -39.1021) -> (102.544, -38.5345)
  line L6955 (108.727, -36.169) -> (109.084, -35.7057)
  line L6956 (98.4456, -33.633) -> (97.9179, -33.3606)
  line L6957 (118.005, -32.6077) -> (118.571, -32.7506)
  line L6958 (107.277, -39.3373) -> (107.432, -38.7738)
  line L6959 (120.711, -33.6764) -> (121.203, -33.9917)
  line L6960 (85.0347, -41.071) -> (85.078, -40.4883)
  line L6961 (107.078, -40.4883) -> (107.159, -39.9096)
  line L6962 (85.1309, -42.8189) -> (85.0612, -42.2388)
  line L6963 (112.295, -33.228) -> (112.834, -33.0011)
  line L6964 (101.879, -45.846) -> (102.153, -45.3193)
  line L6965 (122.543, -35.118) -> (122.938, -35.5485)
  line L6966 (86.8876, -46.7892) -> (87.2572, -47.2539)
  line L6967 (85.9088, -37.7791) -> (85.6834, -38.3285)
  line L6968 (102.855, -39.68) -> (102.719, -39.1021)
  line L6969 (90.4345, -33.2692) -> (89.9003, -33.5286)
  line L6970 (96.3945, -50.0999) -> (96.9627, -49.9272)
  line L6971 (115.682, -32.4086) -> (116.266, -32.402)
  line L6972 (90.9847, -33.0458) -> (90.4345, -33.2692)
  line L6973 (91.5484, -32.8593) -> (90.9847, -33.0458)
  line L6974 (88.0847, -48.1049) -> (88.539, -48.4873)
  line L6975 (92.8615, -50.3221) -> (93.4521, -50.3832)
  line L6976 (98.954, -33.9397) -> (98.4456, -33.633)
  line L6977 (99.5654, -48.5258) -> (100.022, -48.1465)
  line L6978 (92.2761, -50.2221) -> (92.8615, -50.3221)
  line L6979 (119.671, -33.1443) -> (120.199, -33.3936)
  line L6980 (92.1233, -32.7107) -> (91.5484, -32.8593)
  line L6981 (102.885, -43.0665) -> (102.972, -42.4793)
  line L6982 (94.0455, -50.4049) -> (94.6391, -50.3873)
  line L6983 (94.483, -32.5042) -> (93.8893, -32.497)
  line L6984 (85.2379, -43.3934) -> (85.1309, -42.8189)
  line L6985 (85.3803, -43.5861) -> (85.541, -44.1577)
  line L6986 (85.3443, -39.466) -> (85.2321, -40.0491)
  line L6987 (85.1297, -41.825) -> (85.1742, -42.4171)
  line L6988 (88.8893, -34.1505) -> (88.417, -34.5104)
  line L6989 (87.2572, -47.2539) -> (87.6569, -47.6931)
  line L6990 (85.1587, -40.6384) -> (85.1245, -41.2312)
  line L6991 (102.332, -37.9798) -> (102.084, -37.4403)
  line L6992 (88.417, -34.5104) -> (87.9695, -34.9007)
  line L6993 (123.641, -36.4813) -> (123.946, -36.9798)
  line L6994 (99.9045, -34.6507) -> (99.4411, -34.2794)
  line L6995 (102.084, -37.4403) -> (101.801, -36.9185)
  line L6996 (89.5183, -49.1579) -> (90.0392, -49.4431)
  line L6997 (123.946, -36.9798) -> (124.218, -37.4969)
  line L6998 (85.3817, -43.9597) -> (85.2379, -43.3934)
  line L6999 (85.1742, -42.4171) -> (85.2578, -43.005)
  line L7000 (85.7392, -44.7175) -> (85.9741, -45.2629)
  line L7001 (113.386, -32.8094) -> (113.949, -32.6538)
  line L7002 (116.85, -32.4331) -> (117.43, -32.5018)
  line L7003 (85.0332, -41.2312) -> (85.0347, -41.071)
  line L7004 (96.9627, -49.9272) -> (97.5182, -49.7173)
  line L7005 (86.0276, -45.5867) -> (85.7774, -45.0587)
  line L7006 (90.0392, -49.4431) -> (90.5778, -49.6931)
  line L7007 (98.5813, -49.1896) -> (99.0844, -48.874)
  line L7008 (85.0291, -41.6553) -> (85.0332, -41.2312)
  line L7009 (110.783, -34.1099) -> (111.268, -33.7835)
  line L7010 (95.6626, -32.6365) -> (95.075, -32.5508)
  line L7011 (85.5618, -44.5156) -> (85.3817, -43.9597)
  line L7012 (101.229, -46.8393) -> (101.57, -46.3534)
  line L7013 (115.099, -32.4529) -> (115.682, -32.4086)
  line L7014 (85.495, -38.8917) -> (85.3443, -39.466)
  line L7015 (86.7955, -36.2371) -> (86.466, -36.7311)
  line L7016 (93.2963, -32.5291) -> (92.7068, -32.6004)
  line L7017 (100.453, -47.7378) -> (100.856, -47.3014)
  line L7018 (116.266, -32.402) -> (116.85, -32.4331)
  line L7019 (101.57, -46.3534) -> (101.879, -45.846)
  line L7020 (95.2302, -50.3304) -> (95.8162, -50.2345)
  line L7021 (118.571, -32.7506) -> (119.128, -32.9297)
  line L7022 (102.153, -45.3193) -> (102.391, -44.7756)
  line L7023 (86.6274, -46.589) -> (86.3113, -46.0975)
  line L7024 (87.7561, -47.927) -> (87.3513, -47.5056)
  line L7025 (107.159, -39.9096) -> (107.277, -39.3373)
  line L7026 (96.8143, -32.9237) -> (96.2432, -32.761)
  line L7027 (91.1318, -49.9069) -> (91.6987, -50.0835)
  line L7028 (101.801, -36.9185) -> (101.483, -36.4165)
  line L7029 (97.9179, -33.3606) -> (97.3734, -33.1239)
  line L7030 (98.0585, -49.4711) -> (98.5813, -49.1896)
  line L7031 (87.6569, -47.6931) -> (88.0847, -48.1049)
  line L7032 (97.3734, -33.1239) -> (96.8143, -32.9237)
  line L7033 (109.469, -35.2664) -> (109.882, -34.8528)
  line L7034 (87.9695, -34.9007) -> (87.5489, -35.3199)
  line L7035 (97.5182, -49.7173) -> (98.0585, -49.4711)
  line L7036 (103.021, -41.8875) -> (103.032, -41.45)
  line L7037 (86.466, -36.7311) -> (86.17, -37.2459)
  line L7038 (109.882, -34.8528) -> (110.32, -34.4668)
  line L7039 (100.342, -35.0519) -> (99.9045, -34.6507)
  line L7040 (101.133, -35.9368) -> (100.753, -35.4812)
  line L7041 (89.3845, -33.8228) -> (88.8893, -34.1505)
  line L7042 (102.544, -38.5345) -> (102.332, -37.9798)
  line L7043 (86.9746, -47.059) -> (86.6274, -46.589)
  line L7044 (88.539, -48.4873) -> (89.0175, -48.8389)
  line L7045 (85.541, -44.1577) -> (85.7392, -44.7175)
  line L7046 (95.075, -32.5508) -> (94.483, -32.5042)
  line L7047 (86.5495, -46.301) -> (86.8876, -46.7892)
  line L7048 (85.1245, -41.2312) -> (85.1297, -41.825)
  line L7049 (117.43, -32.5018) -> (118.005, -32.6077)
  line L7050 (102.391, -44.7756) -> (102.594, -44.2172)
  line L7051 (95.8162, -50.2345) -> (96.3945, -50.0999)
  line L7052 (102.594, -44.2172) -> (102.758, -43.6467)
  line L7053 (100.022, -48.1465) -> (100.453, -47.7378)
  line L7054 (86.17, -37.2459) -> (85.9088, -37.7791)
  line L7055 (94.6391, -50.3873) -> (95.2302, -50.3304)
  line L7056 (86.3113, -46.0975) -> (86.0276, -45.5867)
  line L7057 (122.938, -35.5485) -> (123.304, -36.0036)
  line L7058 (85.2321, -40.0491) -> (85.1587, -40.6384)
  line L7059 (90.5778, -49.6931) -> (91.1318, -49.9069)
  line L7060 (112.834, -33.0011) -> (113.386, -32.8094)
  line L7061 (93.8893, -32.497) -> (93.2963, -32.5291)
  line L7062 (102.972, -42.4793) -> (103.021, -41.8875)
  line L7063 (100.856, -47.3014) -> (101.229, -46.8393)
  line L7064 (87.157, -35.766) -> (86.7955, -36.2371)
  line L7065 (92.7068, -32.6004) -> (92.1233, -32.7107)
  line L7066 (119.128, -32.9297) -> (119.671, -33.1443)
  line L7067 (99.0844, -48.874) -> (99.5654, -48.5258)
  line L7068 (87.3513, -47.5056) -> (86.9746, -47.059)
  line L7069 (85.2578, -43.005) -> (85.3803, -43.5861)
  line L7070 (96.2432, -32.761) -> (95.6626, -32.6365)
  line L7071 (123.304, -36.0036) -> (123.641, -36.4813)
  line L7072 (101.483, -36.4165) -> (101.133, -35.9368)
  line L7073 (160.046, -145.205) -> (160.639, -145.187)
  line L7074 (90.0392, -144.243) -> (90.5778, -144.493)
  line L7075 (59.0274, -137.588) -> (58.9224, -138.162)
  line L7076 (169.125, -136.424) -> (169.095, -137.007)
  line L7077 (54.5607, -144.111) -> (54.0441, -144.384)
  line L7078 (158.521, -127.335) -> (159.099, -127.253)
  line L7079 (85.5618, -139.316) -> (85.3817, -138.76)
  line L7080 (41.4315, -133.574) -> (41.6223, -133.022)
  line L7081 (94.0455, -145.205) -> (94.6391, -145.187)
  line L7082 (96.9627, -144.727) -> (97.5182, -144.517)
  line L7083 (102.594, -139.017) -> (102.758, -138.447)
  line L7084 (57.1986, -141.834) -> (56.8234, -142.282)
  line L7085 (109.549, -35.3199) -> (109.157, -35.766)
  line L7086 (153.882, -129.653) -> (154.32, -129.267)
  line L7087 (110.417, -34.5104) -> (109.97, -34.9007)
  line L7088 (54.7108, -128.476) -> (55.2028, -128.792)
  line L7089 (86.3113, -140.898) -> (86.0276, -140.387)
  line L7090 (154.539, -143.287) -> (155.018, -143.639)
  line L7091 (151.258, -137.805) -> (151.38, -138.386)
  line L7092 (168.594, -139.017) -> (168.758, -138.447)
  line L7093 (92.8615, -145.122) -> (93.4521, -145.183)
  line L7094 (162.243, -127.561) -> (161.663, -127.437)
  line L7095 (92.1233, -127.511) -> (91.5484, -127.659)
  line L7096 (154.085, -142.905) -> (154.539, -143.287)
  line L7097 (162.814, -127.724) -> (162.243, -127.561)
  line L7098 (58.7806, -138.729) -> (58.6024, -139.286)
  line L7099 (102.758, -138.447) -> (102.885, -137.867)
  line L7100 (166.856, -142.101) -> (167.229, -141.639)
  line L7101 (169.012, -135.657) -> (168.953, -135.066)
  line L7102 (97.5182, -144.517) -> (98.0585, -144.271)
  line L7103 (167.229, -141.639) -> (167.57, -141.153)
  line L7104 (44.7829, -128.91) -> (45.2676, -128.584)
  line L7105 (107.124, -41.2312) -> (107.13, -41.825)
  line L7106 (85.9088, -132.579) -> (85.6834, -133.129)
  line L7107 (155.121, -143.823) -> (154.643, -143.487)
  line L7108 (102.855, -134.48) -> (102.719, -133.902)
  line L7109 (85.1742, -137.217) -> (85.2578, -137.805)
  line L7110 (166.938, -130.349) -> (167.304, -130.804)
  line L7111 (92.7068, -127.4) -> (92.1233, -127.511)
  line L7112 (165.203, -128.792) -> (165.673, -129.138)
  line L7113 (102.153, -140.119) -> (102.391, -139.576)
  line L7114 (86.466, -131.531) -> (86.17, -132.046)
  line L7115 (107.232, -40.0491) -> (107.159, -40.6384)
  line L7116 (156.985, -127.846) -> (156.434, -128.069)
  line L7117 (152.727, -130.969) -> (153.084, -130.506)
  line L7118 (100.856, -142.101) -> (101.229, -141.639)
  line L7119 (168.827, -133.938) -> (168.957, -134.508)
  line L7120 (98.4456, -128.433) -> (97.9179, -128.161)
  line L7121 (162.963, -144.827) -> (162.404, -144.996)
  line L7122 (85.2379, -138.193) -> (85.1309, -137.619)
  line L7123 (152.028, -140.387) -> (151.777, -139.859)
  line L7124 (58.2178, -132.297) -> (58.4559, -132.831)
  line L7125 (41.2769, -134.137) -> (41.4315, -133.574)
  line L7126 (158.861, -145.122) -> (159.452, -145.183)
  line L7127 (160.093, -145.3) -> (159.509, -145.282)
  line L7128 (161.835, -145.128) -> (161.258, -145.223)
  line L7129 (151.159, -135.438) -> (151.124, -136.031)
  line L7130 (151.974, -140.063) -> (152.245, -140.591)
  line L7131 (168.332, -132.78) -> (168.084, -132.24)
  line L7132 (100.342, -129.852) -> (99.9045, -129.451)
  line L7133 (58.6591, -133.378) -> (58.8266, -133.938)
  line L7134 (161.43, -127.302) -> (162.005, -127.408)
  line L7135 (155.385, -128.623) -> (154.889, -128.951)
  line L7136 (158.35, -145.134) -> (157.78, -145.004)
  line L7137 (58.6024, -139.286) -> (58.3887, -139.83)
  line L7138 (151.562, -139.316) -> (151.382, -138.76)
  line L7139 (163.671, -127.944) -> (164.199, -128.194)
  line L7140 (152.402, -131.454) -> (152.727, -130.969)
  line L7141 (151.029, -136.455) -> (151.033, -136.031)
  line L7142 (152.466, -131.531) -> (152.17, -132.046)
  line L7143 (92.2761, -145.022) -> (92.8615, -145.122)
  line L7144 (87.6569, -142.493) -> (88.0847, -142.905)
  line L7145 (157.699, -144.883) -> (158.276, -145.022)
  line L7146 (48.5208, -127.335) -> (49.0994, -127.253)
  line L7147 (100.022, -142.947) -> (100.453, -142.538)
  line L7148 (53.1275, -127.73) -> (53.671, -127.944)
  line L7149 (86.2446, -140.591) -> (86.5495, -141.101)
  line L7150 (168.922, -138.162) -> (168.781, -138.729)
  line L7151 (88.417, -129.31) -> (87.9695, -129.701)
  line L7152 (151.495, -133.692) -> (151.344, -134.266)
  line L7153 (165.084, -143.674) -> (165.565, -143.326)
  line L7154 (168.544, -133.335) -> (168.332, -132.78)
  line L7155 (99.0844, -143.674) -> (99.5654, -143.326)
  line L7156 (95.8162, -145.034) -> (96.3945, -144.9)
  line L7157 (167.858, -140.87) -> (167.544, -141.363)
  line L7158 (108.17, -37.2459) -> (107.909, -37.7791)
  line L7159 (89.3845, -128.623) -> (88.8893, -128.951)
  line L7160 (86.8876, -141.589) -> (87.2572, -142.054)
  line L7161 (85.0612, -137.039) -> (85.0291, -136.455)
  line L7162 (85.6834, -133.129) -> (85.495, -133.692)
  line L7163 (152.245, -140.591) -> (152.55, -141.101)
  line L7164 (86.7955, -131.037) -> (86.466, -131.531)
  line L7165 (161.23, -145.13) -> (161.816, -145.034)
  line L7166 (51.8346, -145.128) -> (51.2581, -145.223)
  line L7167 (58.9575, -134.508) -> (59.0514, -135.084)
  line L7168 (41.6223, -133.022) -> (41.8482, -132.483)
  line L7169 (154.417, -129.31) -> (153.97, -129.701)
  line L7170 (151.432, -133.574) -> (151.622, -133.022)
  line L7171 (160.266, -127.202) -> (160.85, -127.233)
  line L7172 (42.1085, -131.96) -> (42.402, -131.454)
  line L7173 (87.9695, -129.701) -> (87.5489, -130.12)
  line L7174 (91.6987, -144.883) -> (92.2761, -145.022)
  line L7175 (89.5183, -143.958) -> (90.0392, -144.243)
  line L7176 (85.3443, -134.266) -> (85.2321, -134.849)
  line L7177 (158.276, -145.022) -> (158.861, -145.122)
  line L7178 (56.42, -142.705) -> (55.9903, -143.101)
  line L7179 (100.753, -130.281) -> (100.342, -129.852)
  line L7180 (96.2432, -127.561) -> (95.6626, -127.437)
  line L7181 (151.848, -132.483) -> (152.108, -131.96)
  line L7182 (85.1297, -136.625) -> (85.1742, -137.217)
  line L7183 (59.0514, -135.084) -> (59.1079, -135.666)
  line L7184 (93.8893, -127.297) -> (93.2963, -127.329)
  line L7185 (164.446, -128.433) -> (163.918, -128.161)
  line L7186 (163.518, -144.517) -> (164.059, -144.271)
  line L7187 (163.918, -128.161) -> (163.373, -127.924)
  line L7188 (162.395, -144.9) -> (162.963, -144.727)
  line L7189 (98.954, -128.74) -> (98.4456, -128.433)
  line L7190 (165.99, -143.101) -> (165.536, -143.468)
  line L7191 (166.022, -142.947) -> (166.453, -142.538)
  line L7192 (107.495, -38.8917) -> (107.344, -39.466)
  line L7193 (166.42, -142.705) -> (165.99, -143.101)
  line L7194 (151.38, -138.386) -> (151.541, -138.958)
  line L7195 (57.6409, -131.281) -> (57.9457, -131.78)
  line L7196 (155.62, -144.127) -> (155.121, -143.823)
  line L7197 (155.018, -143.639) -> (155.518, -143.958)
  line L7198 (58.9224, -138.162) -> (58.7806, -138.729)
  line L7199 (151.174, -137.217) -> (151.258, -137.805)
  line L7200 (49.0994, -127.253) -> (49.682, -127.209)
  line L7201 (57.8585, -140.87) -> (57.5441, -141.363)
  line L7202 (166.342, -129.852) -> (165.904, -129.451)
  line L7203 (103.032, -136.25) -> (103.012, -135.657)
  line L7204 (102.544, -133.335) -> (102.332, -132.78)
  line L7205 (90.5778, -144.493) -> (91.1318, -144.707)
  line L7206 (107.344, -39.466) -> (107.232, -40.0491)
  line L7207 (88.8893, -128.951) -> (88.417, -129.31)
  line L7208 (162.404, -144.996) -> (161.835, -145.128)
  line L7209 (58.3887, -139.83) -> (58.1404, -140.359)
  line L7210 (93.2963, -127.329) -> (92.7068, -127.4)
  line L7211 (42.402, -131.454) -> (42.7274, -130.969)